Autodesk Fusion 360 part; units mm, degrees
(part 5 of 7)
sketch "Sketch16" plane through (0, 0, 15.5) normal (0, 0, 1) x (-1, 0, 0)
  arc A0 (-2.994408, 1.281873) -> (-3.212089, 0.540519) centre (0, 0) ccw
  line L0 (-3.212089, 0.540519) -> (-3.686686, 0.620382)
  spline S0 degree 5 poles (-3.686686, 0.620382) (-3.689992, 0.620938) (-3.696617, 0.621933) (-3.706589, 0.62307) (-3.719953, 0.62391) (-3.736756, 0.624036) (-3.753636, 0.623493) (-3.770571, 0.622533) (-3.787545, 0.621343) (-3.804547, 0.619993) (-3.821576, 0.618478) (-3.83863, 0.616745) (-3.855711, 0.614726) (-3.87282, 0.612373) (-3.889954, 0.609683) (-3.907112, 0.606681) (-3.924288, 0.603406) (-3.941479, 0.599899) (-3.958682, 0.596191) (-3.975894, 0.592292) (-3.993115, 0.5882) (-4.010344, 0.583904) (-4.02758, 0.579395) (-4.044821, 0.574666) (-4.062068, 0.56972) (-4.079318, 0.564562) (-4.096569, 0.559203) (-4.11382, 0.553651) (-4.13107, 0.547913) (-4.148317, 0.541992) (-4.165561, 0.535888) (-4.182799, 0.529602) (-4.200032, 0.523132) (-4.217258, 0.51648) (-4.234476, 0.509646) (-4.251685, 0.502632) (-4.268884, 0.495443) (-4.286072, 0.48808) (-4.303247, 0.480546) (-4.320409, 0.472843) (-4.337557, 0.46497) (-4.35469, 0.45693) (-4.371806, 0.448723) (-4.388905, 0.440351) (-4.405986, 0.431813) (-4.423048, 0.423112) (-4.44009, 0.414249) (-4.457112, 0.405224) (-4.474111, 0.396041) (-4.491087, 0.386698) (-4.50804, 0.377198) (-4.524969, 0.36754) (-4.541872, 0.357727) (-4.558748, 0.347759) (-4.575598, 0.337636) (-4.592419, 0.32736) (-4.609212, 0.316932) (-4.625974, 0.306352) (-4.642706, 0.295621) (-4.659407, 0.28474) (-4.676075, 0.273709) (-4.69271, 0.26253) (-4.709312, 0.251204) (-4.725879, 0.23973) (-4.74241, 0.22811) (-4.758905, 0.216344) (-4.775362, 0.204434) (-4.79178, 0.192379) (-4.80816, 0.180181) (-4.824499, 0.16784) (-4.840799, 0.155357) (-4.853807, 0.145257) (-4.863544, 0.137618) (-4.870028, 0.132497) (-4.873268, 0.12993) knots 0 0 0 0 0 0 0.01428571 0.02857143 0.04285714 0.05714286 0.07142857 0.08571429 0.1 0.11428571 0.12857143 0.14285714 0.15714286 0.17142857 0.18571429 0.2 0.21428571 0.22857143 0.24285714 0.25714286 0.27142857 0.28571429 0.3 0.31428571 0.32857143 0.34285714 0.35714286 0.37142857 0.38571429 0.4 0.41428571 0.42857143 0.44285714 0.45714286 0.47142857 0.48571429 0.5 0.51428571 0.52857143 0.54285714 0.55714286 0.57142857 0.58571429 0.6 0.61428571 0.62857143 0.64285714 0.65714286 0.67142857 0.68571429 0.7 0.71428571 0.72857143 0.74285714 0.75714286 0.77142857 0.78571429 0.8 0.81428571 0.82857143 0.84285714 0.85714286 0.87142857 0.88571429 0.9 0.91428571 0.92857143 0.94285714 0.95714286 0.97142857 0.98571429 1 1 1 1 1 1
  arc A1 (-4.873268, 0.12993) -> (-4.873268, -0.12993) centre (0, 0) ccw
  spline S1 degree 5 poles (-4.873268, -0.12993) (-4.870028, -0.132497) (-4.863544, -0.137618) (-4.853807, -0.145257) (-4.840799, -0.155357) (-4.824499, -0.16784) (-4.80816, -0.180181) (-4.79178, -0.192379) (-4.775362, -0.204434) (-4.758905, -0.216344) (-4.74241, -0.22811) (-4.725879, -0.23973) (-4.709312, -0.251204) (-4.69271, -0.26253) (-4.676075, -0.273709) (-4.659407, -0.28474) (-4.642706, -0.295621) (-4.625974, -0.306352) (-4.609212, -0.316932) (-4.592419, -0.32736) (-4.575598, -0.337636) (-4.558748, -0.347759) (-4.541872, -0.357727) (-4.524969, -0.36754) (-4.50804, -0.377198) (-4.491087, -0.386698) (-4.474111, -0.396041) (-4.457112, -0.405224) (-4.44009, -0.414249) (-4.423048, -0.423112) (-4.405986, -0.431813) (-4.388905, -0.440351) (-4.371806, -0.448723) (-4.35469, -0.45693) (-4.337557, -0.46497) (-4.320409, -0.472843) (-4.303247, -0.480546) (-4.286072, -0.48808) (-4.268884, -0.495443) (-4.251685, -0.502632) (-4.234476, -0.509646) (-4.217258, -0.51648) (-4.200032, -0.523132) (-4.182799, -0.529602) (-4.165561, -0.535888) (-4.148317, -0.541992) (-4.13107, -0.547913) (-4.11382, -0.553651) (-4.096569, -0.559203) (-4.079318, -0.564562) (-4.062068, -0.56972) (-4.044821, -0.574666) (-4.02758, -0.579395) (-4.010344, -0.583904) (-3.993115, -0.5882) (-3.975894, -0.592292) (-3.958682, -0.596191) (-3.941479, -0.599899) (-3.924288, -0.603406) (-3.907112, -0.606681) (-3.889954, -0.609683) (-3.87282, -0.612373) (-3.855711, -0.614726) (-3.83863, -0.616745) (-3.821576, -0.618478) (-3.804547, -0.619993) (-3.787545, -0.621343) (-3.770571, -0.622533) (-3.753636, -0.623493) (-3.736756, -0.624036) (-3.719953, -0.62391) (-3.706589, -0.62307) (-3.696617, -0.621933) (-3.689992, -0.620938) (-3.686686, -0.620382) knots -1 -1 -1 -1 -1 -1 -0.98571429 -0.97142857 -0.95714286 -0.94285714 -0.92857143 -0.91428571 -0.9 -0.88571429 -0.87142857 -0.85714286 -0.84285714 -0.82857143 -0.81428571 -0.8 -0.78571429 -0.77142857 -0.75714286 -0.74285714 -0.72857143 -0.71428571 -0.7 -0.68571429 -0.67142857 -0.65714286 -0.64285714 -0.62857143 -0.61428571 -0.6 -0.58571429 -0.57142857 -0.55714286 -0.54285714 -0.52857143 -0.51428571 -0.5 -0.48571429 -0.47142857 -0.45714286 -0.44285714 -0.42857143 -0.41428571 -0.4 -0.38571429 -0.37142857 -0.35714286 -0.34285714 -0.32857143 -0.31428571 -0.3 -0.28571429 -0.27142857 -0.25714286 -0.24285714 -0.22857143 -0.21428571 -0.2 -0.18571429 -0.17142857 -0.15714286 -0.14285714 -0.12857143 -0.11428571 -0.1 -0.08571429 -0.07142857 -0.05714286 -0.04285714 -0.02857143 -0.01428571 0 0 0 0 0 0
  line L1 (-3.686686, -0.620382) -> (-3.212089, -0.540519)
  arc A2 (-3.212089, -0.540519) -> (-2.994408, -1.281873) centre (0, 0) ccw
  line L2 (-2.994408, -1.281873) -> (-3.436842, -1.471275)
  spline S2 degree 5 poles (-3.436842, -1.471275) (-3.439924, -1.472594) (-3.446034, -1.475339) (-3.455038, -1.479774) (-3.466735, -1.486292) (-3.480939, -1.49527) (-3.494845, -1.504853) (-3.508573, -1.514816) (-3.522209, -1.524994) (-3.535783, -1.535322) (-3.549289, -1.545803) (-3.562699, -1.556481) (-3.575976, -1.567415) (-3.589097, -1.578644) (-3.602057, -1.59017) (-3.614868, -1.601972) (-3.627547, -1.614013) (-3.640113, -1.626257) (-3.652581, -1.638677) (-3.664953, -1.651263) (-3.677227, -1.664016) (-3.689398, -1.676944) (-3.70146, -1.690056) (-3.713408, -1.703356) (-3.725243, -1.716841) (-3.736966, -1.730506) (-3.748581, -1.744341) (-3.760092, -1.758338) (-3.771502, -1.772491) (-3.78281, -1.786797) (-3.794016, -1.801254) (-3.805119, -1.815862) (-3.816119, -1.830622) (-3.827013, -1.845531) (-3.837803, -1.860589) (-3.848489, -1.875793) (-3.85907, -1.89114) (-3.869549, -1.906626) (-3.879925, -1.92225) (-3.890197, -1.938009) (-3.900367, -1.953902) (-3.910433, -1.969929) (-3.920395, -1.986087) (-3.930253, -2.002375) (-3.940007, -2.018792) (-3.949657, -2.035336) (-3.959202, -2.052006) (-3.968642, -2.0688) (-3.977977, -2.085716) (-3.987208, -2.102754) (-3.996333, -2.119912) (-4.005353, -2.137188) (-4.014268, -2.154582) (-4.023076, -2.172092) (-4.031778, -2.189717) (-4.040373, -2.207456) (-4.048862, -2.225308) (-4.057243, -2.243271) (-4.065518, -2.261345) (-4.073684, -2.279527) (-4.081743, -2.297818) (-4.089694, -2.316216) (-4.097536, -2.33472) (-4.10527, -2.35333) (-4.112895, -2.372043) (-4.12041, -2.390858) (-4.127815, -2.409775) (-4.13511, -2.428793) (-4.142295, -2.447909) (-4.149368, -2.467125) (-4.156332, -2.486438) (-4.161814, -2.501968) (-4.165876, -2.513659) (-4.168562, -2.521472) (-4.1699, -2.525384) knots 0 0 0 0 0 0 0.01428571 0.02857143 0.04285714 0.05714286 0.07142857 0.08571429 0.1 0.11428571 0.12857143 0.14285714 0.15714286 0.17142857 0.18571429 0.2 0.21428571 0.22857143 0.24285714 0.25714286 0.27142857 0.28571429 0.3 0.31428571 0.32857143 0.34285714 0.35714286 0.37142857 0.38571429 0.4 0.41428571 0.42857143 0.44285714 0.45714286 0.47142857 0.48571429 0.5 0.51428571 0.52857143 0.54285714 0.55714286 0.57142857 0.58571429 0.6 0.61428571 0.62857143 0.64285714 0.65714286 0.67142857 0.68571429 0.7 0.71428571 0.72857143 0.74285714 0.75714286 0.77142857 0.78571429 0.8 0.81428571 0.82857143 0.84285714 0.85714286 0.87142857 0.88571429 0.9 0.91428571 0.92857143 0.94285714 0.95714286 0.97142857 0.98571429 1 1 1 1 1 1
  arc A3 (-4.1699, -2.525384) -> (-4.029409, -2.743992) centre (0, 0) ccw
  spline S3 degree 5 poles (-4.029409, -2.743992) (-4.025295, -2.7444) (-4.017072, -2.745203) (-4.00475, -2.746364) (-3.988346, -2.747828) (-3.967886, -2.749518) (-3.947468, -2.751065) (-3.927094, -2.752472) (-3.906765, -2.753736) (-3.886481, -2.754858) (-3.866244, -2.755839) (-3.846055, -2.756677) (-3.825914, -2.757372) (-3.805825, -2.757925) (-3.785786, -2.758336) (-3.765801, -2.758604) (-3.745869, -2.758728) (-3.725991, -2.75871) (-3.70617, -2.758548) (-3.686405, -2.758242) (-3.666698, -2.757793) (-3.647051, -2.757199) (-3.627464, -2.756461) (-3.607939, -2.755578) (-3.588476, -2.75455) (-3.569078, -2.753376) (-3.549746, -2.752057) (-3.53048, -2.750593) (-3.511282, -2.748982) (-3.492154, -2.747225) (-3.473096, -2.74532) (-3.45411, -2.743268) (-3.435199, -2.741067) (-3.416363, -2.738717) (-3.397603, -2.736218) (-3.378921, -2.73357) (-3.360319, -2.730772) (-3.341797, -2.727825) (-3.323357, -2.724726) (-3.305001, -2.721476) (-3.286733, -2.718072) (-3.268553, -2.714512) (-3.250465, -2.710796) (-3.23247, -2.706922) (-3.21457, -2.70289) (-3.196764, -2.698702) (-3.179053, -2.694359) (-3.16144, -2.68986) (-3.143925, -2.685204) (-3.126515, -2.680386) (-3.109215, -2.675398) (-3.092032, -2.670235) (-3.074971, -2.664892) (-3.058034, -2.659367) (-3.041218, -2.653666) (-3.024518, -2.647799) (-3.00793, -2.641773) (-2.991453, -2.635592) (-2.975095, -2.629247) (-2.958875, -2.622717) (-2.942818, -2.615966) (-2.92695, -2.608965) (-2.911285, -2.601695) (-2.895823, -2.594159) (-2.880539, -2.586397) (-2.865395, -2.578465) (-2.850362, -2.570408) (-2.835439, -2.562233) (-2.820673, -2.553885) (-2.80618, -2.545216) (-2.792112, -2.536025) (-2.781324, -2.528093) (-2.77355, -2.521745) (-2.768515, -2.517327) (-2.766034, -2.515072) knots -1 -1 -1 -1 -1 -1 -0.98571429 -0.97142857 -0.95714286 -0.94285714 -0.92857143 -0.91428571 -0.9 -0.88571429 -0.87142857 -0.85714286 -0.84285714 -0.82857143 -0.81428571 -0.8 -0.78571429 -0.77142857 -0.75714286 -0.74285714 -0.72857143 -0.71428571 -0.7 -0.68571429 -0.67142857 -0.65714286 -0.64285714 -0.62857143 -0.61428571 -0.6 -0.58571429 -0.57142857 -0.55714286 -0.54285714 -0.52857143 -0.51428571 -0.5 -0.48571429 -0.47142857 -0.45714286 -0.44285714 -0.42857143 -0.41428571 -0.4 -0.38571429 -0.37142857 -0.35714286 -0.34285714 -0.32857143 -0.31428571 -0.3 -0.28571429 -0.27142857 -0.25714286 -0.24285714 -0.22857143 -0.21428571 -0.2 -0.18571429 -0.17142857 -0.15714286 -0.14285714 -0.12857143 -0.11428571 -0.1 -0.08571429 -0.07142857 -0.05714286 -0.04285714 -0.02857143 -0.01428571 0 0 0 0 0 0
  line L3 (-2.766034, -2.515072) -> (-2.409955, -2.1913)
  arc A4 (-2.409955, -2.1913) -> (-1.826023, -2.69728) centre (0, 0) ccw
  line L4 (-1.826023, -2.69728) -> (-2.095824, -3.095812)
  spline S4 degree 5 poles (-2.095824, -3.095812) (-2.097704, -3.098588) (-2.10136, -3.104201) (-2.106537, -3.112799) (-2.112853, -3.124607) (-2.119948, -3.139839) (-2.126466, -3.155419) (-2.132628, -3.171222) (-2.138596, -3.187157) (-2.144432, -3.203184) (-2.150128, -3.219302) (-2.155636, -3.235535) (-2.160894, -3.251912) (-2.165861, -3.268452) (-2.170533, -3.285156) (-2.174929, -3.30201) (-2.179085, -3.318994) (-2.183037, -3.336088) (-2.186811, -3.353277) (-2.190414, -3.370554) (-2.193845, -3.387919) (-2.197095, -3.405375) (-2.200153, -3.422926) (-2.203014, -3.440574) (-2.205679, -3.458317) (-2.208154, -3.47615) (-2.210445, -3.494069) (-2.212562, -3.512068) (-2.214508, -3.530142) (-2.216286, -3.548291) (-2.217898, -3.566511) (-2.219341, -3.584803) (-2.220614, -3.603166) (-2.221719, -3.621599) (-2.222655, -3.6401) (-2.223424, -3.658668) (-2.224029, -3.677299) (-2.224472, -3.695992) (-2.224754, -3.714745) (-2.224875, -3.733556) (-2.224838, -3.752425) (-2.224642, -3.771349) (-2.224287, -3.790328) (-2.223774, -3.80936) (-2.223104, -3.828444) (-2.222277, -3.847579) (-2.221294, -3.866763) (-2.220156, -3.885995) (-2.218864, -3.905273) (-2.217418, -3.924597) (-2.215819, -3.943964) (-2.214067, -3.963375) (-2.212162, -3.982827) (-2.210105, -4.002319) (-2.207897, -4.021851) (-2.205537, -4.041421) (-2.203027, -4.061028) (-2.200366, -4.080671) (-2.197556, -4.100349) (-2.194596, -4.12006) (-2.191486, -4.139805) (-2.188228, -4.15958) (-2.184822, -4.179387) (-2.181267, -4.199223) (-2.177564, -4.219088) (-2.173714, -4.23898) (-2.169716, -4.258897) (-2.165572, -4.27884) (-2.16128, -4.298806) (-2.156842, -4.318795) (-2.152259, -4.338808) (-2.148475, -4.354836) (-2.145571, -4.366867) (-2.143607, -4.374892) (-2.142617, -4.378906) knots 0 0 0 0 0 0 0.01428571 0.02857143 0.04285714 0.05714286 0.07142857 0.08571429 0.1 0.11428571 0.12857143 0.14285714 0.15714286 0.17142857 0.18571429 0.2 0.21428571 0.22857143 0.24285714 0.25714286 0.27142857 0.28571429 0.3 0.31428571 0.32857143 0.34285714 0.35714286 0.37142857 0.38571429 0.4 0.41428571 0.42857143 0.44285714 0.45714286 0.47142857 0.48571429 0.5 0.51428571 0.52857143 0.54285714 0.55714286 0.57142857 0.58571429 0.6 0.61428571 0.62857143 0.64285714 0.65714286 0.67142857 0.68571429 0.7 0.71428571 0.72857143 0.74285714 0.75714286 0.77142857 0.78571429 0.8 0.81428571 0.82857143 0.84285714 0.85714286 0.87142857 0.88571429 0.9 0.91428571 0.92857143 0.94285714 0.95714286 0.97142857 0.98571429 1 1 1 1 1 1
  arc A5 (-2.142617, -4.378906) -> (-1.90624, -4.486856) centre (0, 0) ccw
  spline S5 degree 5 poles (-1.90624, -4.486856) (-1.902559, -4.484975) (-1.895207, -4.481204) (-1.884213, -4.47552) (-1.869622, -4.467883) (-1.851496, -4.458242) (-1.833483, -4.448506) (-1.815583, -4.438674) (-1.797798, -4.428747) (-1.780127, -4.418725) (-1.762573, -4.408608) (-1.745135, -4.398398) (-1.727816, -4.388095) (-1.710616, -4.377699) (-1.693537, -4.36721) (-1.676579, -4.356631) (-1.659744, -4.345959) (-1.643032, -4.335197) (-1.626445, -4.324345) (-1.609983, -4.313402) (-1.593647, -4.30237) (-1.57744, -4.291248) (-1.561362, -4.280037) (-1.545413, -4.268738) (-1.529597, -4.257351) (-1.513912, -4.245877) (-1.498362, -4.234316) (-1.482946, -4.222668) (-1.467666, -4.210933) (-1.452525, -4.199113) (-1.437522, -4.187208) (-1.42266, -4.175217) (-1.407941, -4.163141) (-1.393365, -4.150981) (-1.378934, -4.138736) (-1.36465, -4.126408) (-1.350513, -4.113997) (-1.336525, -4.101504) (-1.322688, -4.088928) (-1.309003, -4.07627) (-1.295475, -4.063529) (-1.282106, -4.050706) (-1.268898, -4.037801) (-1.255855, -4.024813) (-1.242975, -4.011743) (-1.23026, -3.998594) (-1.217709, -3.985365) (-1.205324, -3.972058) (-1.193107, -3.958672) (-1.181066, -3.945206) (-1.169209, -3.931657) (-1.157545, -3.918024) (-1.146081, -3.904305) (-1.134819, -3.8905) (-1.123755, -3.876612) (-1.112878, -3.862648) (-1.102181, -3.848611) (-1.091662, -3.834503) (-1.081331, -3.820322) (-1.071217, -3.806058) (-1.061358, -3.791698) (-1.051794, -3.77723) (-1.042546, -3.762644) (-1.033613, -3.747946) (-1.024952, -3.733153) (-1.0165, -3.718293) (-1.00821, -3.703387) (-1.000076, -3.688442) (-0.992167, -3.673436) (-0.984661, -3.658307) (-0.977796, -3.64297) (-0.973009, -3.630464) (-0.9699, -3.620921) (-0.968053, -3.614482) (-0.967186, -3.611244) knots -1 -1 -1 -1 -1 -1 -0.98571429 -0.97142857 -0.95714286 -0.94285714 -0.92857143 -0.91428571 -0.9 -0.88571429 -0.87142857 -0.85714286 -0.84285714 -0.82857143 -0.81428571 -0.8 -0.78571429 -0.77142857 -0.75714286 -0.74285714 -0.72857143 -0.71428571 -0.7 -0.68571429 -0.67142857 -0.65714286 -0.64285714 -0.62857143 -0.61428571 -0.6 -0.58571429 -0.57142857 -0.55714286 -0.54285714 -0.52857143 -0.51428571 -0.5 -0.48571429 -0.47142857 -0.45714286 -0.44285714 -0.42857143 -0.41428571 -0.4 -0.38571429 -0.37142857 -0.35714286 -0.34285714 -0.32857143 -0.31428571 -0.3 -0.28571429 -0.27142857 -0.25714286 -0.24285714 -0.22857143 -0.21428571 -0.2 -0.18571429 -0.17142857 -0.15714286 -0.14285714 -0.12857143 -0.11428571 -0.1 -0.08571429 -0.07142857 -0.05714286 -0.04285714 -0.02857143 -0.01428571 0 0 0 0 0 0
  line L5 (-0.967186, -3.611244) -> (-0.842677, -3.146359)
  arc A6 (-0.842677, -3.146359) -> (-0.077889, -3.256319) centre (0, 0) ccw
  line L6 (-0.077889, -3.256319) -> (-0.089397, -3.737451)
  spline S6 degree 5 poles (-0.089397, -3.737451) (-0.089477, -3.740802) (-0.089519, -3.747501) (-0.089225, -3.757533) (-0.088155, -3.770881) (-0.085889, -3.787531) (-0.082949, -3.804162) (-0.079588, -3.820788) (-0.075995, -3.837419) (-0.072239, -3.854057) (-0.068316, -3.870696) (-0.064174, -3.88733) (-0.059744, -3.90395) (-0.05498, -3.92055) (-0.049879, -3.937127) (-0.044466, -3.953683) (-0.038779, -3.970218) (-0.032862, -3.986735) (-0.026744, -4.003235) (-0.020435, -4.019718) (-0.013933, -4.036181) (-0.007229, -4.052623) (-0.000313, -4.069041) (0.006821, -4.085434) (0.014172, -4.101801) (0.021731, -4.118142) (0.029491, -4.134455) (0.037442, -4.15074) (0.045577, -4.166998) (0.053892, -4.183227) (0.062387, -4.199426) (0.071063, -4.215595) (0.079919, -4.231731) (0.088956, -4.247835) (0.098171, -4.263905) (0.107561, -4.279941) (0.117125, -4.295942) (0.126859, -4.311907) (0.136761, -4.327835) (0.146829, -4.343726) (0.157061, -4.359579) (0.167458, -4.375393) (0.178017, -4.391167) (0.188738, -4.406901) (0.199619, -4.422593) (0.21066, -4.438243) (0.221859, -4.45385) (0.233213, -4.469414) (0.244723, -4.484933) (0.256386, -4.500408) (0.268203, -4.515836) (0.280171, -4.531218) (0.29229, -4.546552) (0.304558, -4.561838) (0.316976, -4.577076) (0.329541, -4.592263) (0.342253, -4.607401) (0.355111, -4.622487) (0.368114, -4.637521) (0.381261, -4.652503) (0.394552, -4.667432) (0.407984, -4.682307) (0.421558, -4.697128) (0.435273, -4.711894) (0.449128, -4.726603) (0.463121, -4.741255) (0.477252, -4.75585) (0.491521, -4.770385) (0.505925, -4.784862) (0.520466, -4.799279) (0.535141, -4.813636) (0.54699, -4.825074) (0.555937, -4.833626) (0.561928, -4.839315) (0.564931, -4.842156) knots 0 0 0 0 0 0 0.01428571 0.02857143 0.04285714 0.05714286 0.07142857 0.08571429 0.1 0.11428571 0.12857143 0.14285714 0.15714286 0.17142857 0.18571429 0.2 0.21428571 0.22857143 0.24285714 0.25714286 0.27142857 0.28571429 0.3 0.31428571 0.32857143 0.34285714 0.35714286 0.37142857 0.38571429 0.4 0.41428571 0.42857143 0.44285714 0.45714286 0.47142857 0.48571429 0.5 0.51428571 0.52857143 0.54285714 0.55714286 0.57142857 0.58571429 0.6 0.61428571 0.62857143 0.64285714 0.65714286 0.67142857 0.68571429 0.7 0.71428571 0.72857143 0.74285714 0.75714286 0.77142857 0.78571429 0.8 0.81428571 0.82857143 0.84285714 0.85714286 0.87142857 0.88571429 0.9 0.91428571 0.92857143 0.94285714 0.95714286 0.97142857 0.98571429 1 1 1 1 1 1
  arc A7 (0.564931, -4.842156) -> (0.822146, -4.805174) centre (0, 0) ccw
  spline S7 degree 5 poles (0.822146, -4.805174) (0.824226, -4.801602) (0.828372, -4.794455) (0.834548, -4.783729) (0.842694, -4.769417) (0.85273, -4.751506) (0.86262, -4.733577) (0.872362, -4.715629) (0.881958, -4.697662) (0.891405, -4.679677) (0.900703, -4.661676) (0.909852, -4.643659) (0.918852, -4.625628) (0.927701, -4.607583) (0.936398, -4.589526) (0.944944, -4.571458) (0.953338, -4.553379) (0.961578, -4.53529) (0.969665, -4.517193) (0.977598, -4.499087) (0.985375, -4.480974) (0.992997, -4.462856) (1.000462, -4.444732) (1.00777, -4.426605) (1.014919, -4.408474) (1.02191, -4.390342) (1.028742, -4.372208) (1.035413, -4.354075) (1.041923, -4.335943) (1.048271, -4.317813) (1.054455, -4.299686) (1.060475, -4.281564) (1.066329, -4.263447) (1.072016, -4.245337) (1.077536, -4.227235) (1.082888, -4.209141) (1.088071, -4.191057) (1.093084, -4.172985) (1.097926, -4.154924) (1.102594, -4.136877) (1.107087, -4.118845) (1.111401, -4.10083) (1.115535, -4.082832) (1.119486, -4.064854) (1.123255, -4.046897) (1.126842, -4.02896) (1.130249, -4.011046) (1.133473, -3.993155) (1.136514, -3.975289) (1.139363, -3.95745) (1.142013, -3.939642) (1.144455, -3.921867) (1.146682, -3.904128) (1.148692, -3.886426) (1.150492, -3.868762) (1.152092, -3.851134) (1.153502, -3.833541) (1.154724, -3.815986) (1.155748, -3.798471) (1.156546, -3.781003) (1.157076, -3.763593) (1.157299, -3.74625) (1.157194, -3.728981) (1.156762, -3.711786) (1.15605, -3.694659) (1.155126, -3.677588) (1.154042, -3.660567) (1.152805, -3.643596) (1.151345, -3.626697) (1.14948, -3.609912) (1.146964, -3.593298) (1.14423, -3.580189) (1.141686, -3.57048) (1.139759, -3.564065) (1.138738, -3.560872) knots -1 -1 -1 -1 -1 -1 -0.98571429 -0.97142857 -0.95714286 -0.94285714 -0.92857143 -0.91428571 -0.9 -0.88571429 -0.87142857 -0.85714286 -0.84285714 -0.82857143 -0.81428571 -0.8 -0.78571429 -0.77142857 -0.75714286 -0.74285714 -0.72857143 -0.71428571 -0.7 -0.68571429 -0.67142857 -0.65714286 -0.64285714 -0.62857143 -0.61428571 -0.6 -0.58571429 -0.57142857 -0.55714286 -0.54285714 -0.52857143 -0.51428571 -0.5 -0.48571429 -0.47142857 -0.45714286 -0.44285714 -0.42857143 -0.41428571 -0.4 -0.38571429 -0.37142857 -0.35714286 -0.34285714 -0.32857143 -0.31428571 -0.3 -0.28571429 -0.27142857 -0.25714286 -0.24285714 -0.22857143 -0.21428571 -0.2 -0.18571429 -0.17142857 -0.15714286 -0.14285714 -0.12857143 -0.11428571 -0.1 -0.08571429 -0.07142857 -0.05714286 -0.04285714 -0.02857143 -0.01428571 0 0 0 0 0 0
  line L7 (1.138738, -3.560872) -> (0.992145, -3.102471)
  arc A8 (0.992145, -3.102471) -> (1.694974, -2.781499) centre (0, 0) ccw
  line L8 (1.694974, -2.781499) -> (1.945413, -3.192475)
  spline S8 degree 5 poles (1.945413, -3.192475) (1.947157, -3.195338) (1.950744, -3.200996) (1.956415, -3.209277) (1.964531, -3.219927) (1.97544, -3.232709) (1.986904, -3.24511) (1.99872, -3.25728) (2.010735, -3.269328) (2.022889, -3.281294) (2.035185, -3.293172) (2.047663, -3.304925) (2.060375, -3.316512) (2.073357, -3.327901) (2.086611, -3.339089) (2.100115, -3.35009) (2.113839, -3.360926) (2.127746, -3.371622) (2.141814, -3.382195) (2.156033, -3.392649) (2.170403, -3.402984) (2.184932, -3.413192) (2.199626, -3.423264) (2.214491, -3.433198) (2.229523, -3.442993) (2.244717, -3.452652) (2.260065, -3.462181) (2.275558, -3.471582) (2.291191, -3.480861) (2.30696, -3.490018) (2.322865, -3.499053) (2.338905, -3.507964) (2.355079, -3.516751) (2.371387, -3.525413) (2.387828, -3.53395) (2.404397, -3.542363) (2.421094, -3.550653) (2.437914, -3.558821) (2.454855, -3.566868) (2.471916, -3.574793) (2.489095, -3.582598) (2.50639, -3.59028) (2.523801, -3.597842) (2.541327, -3.605282) (2.558965, -3.6126) (2.576714, -3.619796) (2.594573, -3.626872) (2.612539, -3.633826) (2.630612, -3.640659) (2.64879, -3.647371) (2.667072, -3.653962) (2.685456, -3.660431) (2.703941, -3.666779) (2.722527, -3.673006) (2.741211, -3.679111) (2.759993, -3.685094) (2.778871, -3.690956) (2.797844, -3.696696) (2.816911, -3.702314) (2.836071, -3.707809) (2.855322, -3.713183) (2.874665, -3.718435) (2.894096, -3.723564) (2.913617, -3.728571) (2.933225, -3.733455) (2.952918, -3.738216) (2.972697, -3.742853) (2.992558, -3.747368) (3.012503, -3.751758) (3.03253, -3.756025) (3.052638, -3.760169) (3.068789, -3.763386) (3.080939, -3.765742) (3.089055, -3.767289) (3.093118, -3.768056) knots 0 0 0 0 0 0 0.01428571 0.02857143 0.04285714 0.05714286 0.07142857 0.08571429 0.1 0.11428571 0.12857143 0.14285714 0.15714286 0.17142857 0.18571429 0.2 0.21428571 0.22857143 0.24285714 0.25714286 0.27142857 0.28571429 0.3 0.31428571 0.32857143 0.34285714 0.35714286 0.37142857 0.38571429 0.4 0.41428571 0.42857143 0.44285714 0.45714286 0.47142857 0.48571429 0.5 0.51428571 0.52857143 0.54285714 0.55714286 0.57142857 0.58571429 0.6 0.61428571 0.62857143 0.64285714 0.65714286 0.67142857 0.68571429 0.7 0.71428571 0.72857143 0.74285714 0.75714286 0.77142857 0.78571429 0.8 0.81428571 0.82857143 0.84285714 0.85714286 0.87142857 0.88571429 0.9 0.91428571 0.92857143 0.94285714 0.95714286 0.97142857 0.98571429 1 1 1 1 1 1
  arc A9 (3.093118, -3.768056) -> (3.289506, -3.597884) centre (0, 0) ccw
  spline S9 degree 5 poles (3.289506, -3.597884) (3.289325, -3.593754) (3.288949, -3.585501) (3.288345, -3.573139) (3.28746, -3.556694) (3.28622, -3.536201) (3.284847, -3.515771) (3.283339, -3.495405) (3.281698, -3.475102) (3.279922, -3.454865) (3.278012, -3.434695) (3.275968, -3.414591) (3.273791, -3.394557) (3.271479, -3.374593) (3.269034, -3.3547) (3.266454, -3.33488) (3.263741, -3.315133) (3.260894, -3.295461) (3.257913, -3.275864) (3.254797, -3.256344) (3.251548, -3.236902) (3.248164, -3.217539) (3.244646, -3.198256) (3.240993, -3.179055) (3.237206, -3.159938) (3.233284, -3.140904) (3.229227, -3.121956) (3.225036, -3.103095) (3.220709, -3.084321) (3.216247, -3.065638) (3.21165, -3.047045) (3.206916, -3.028545) (3.202047, -3.010139) (3.19704, -2.991829) (3.191897, -2.973616) (3.186617, -2.955501) (3.1812, -2.937486) (3.175646, -2.919572) (3.169955, -2.901761) (3.164126, -2.884055) (3.158157, -2.866457) (3.152046, -2.848969) (3.145793, -2.831594) (3.139398, -2.814333) (3.132859, -2.797189) (3.12618, -2.78016) (3.119361, -2.763248) (3.112401, -2.746454) (3.1053, -2.72978) (3.098053, -2.713233) (3.090654, -2.696819) (3.083098, -2.680546) (3.075381, -2.664419) (3.067502, -2.64844) (3.059466, -2.632606) (3.051282, -2.616912) (3.042957, -2.60135) (3.034493, -2.585921) (3.025886, -2.570632) (3.017113, -2.555507) (3.008146, -2.540574) (2.998958, -2.525863) (2.989532, -2.511392) (2.979873, -2.497161) (2.970015, -2.483137) (2.960008, -2.469276) (2.949894, -2.455542) (2.939678, -2.441935) (2.929314, -2.428507) (2.91867, -2.415395) (2.907571, -2.402779) (2.898184, -2.393229) (2.890795, -2.386437) (2.885705, -2.382082) (2.883119, -2.379948) knots -1 -1 -1 -1 -1 -1 -0.98571429 -0.97142857 -0.95714286 -0.94285714 -0.92857143 -0.91428571 -0.9 -0.88571429 -0.87142857 -0.85714286 -0.84285714 -0.82857143 -0.81428571 -0.8 -0.78571429 -0.77142857 -0.75714286 -0.74285714 -0.72857143 -0.71428571 -0.7 -0.68571429 -0.67142857 -0.65714286 -0.64285714 -0.62857143 -0.61428571 -0.6 -0.58571429 -0.57142857 -0.55714286 -0.54285714 -0.52857143 -0.51428571 -0.5 -0.48571429 -0.47142857 -0.45714286 -0.44285714 -0.42857143 -0.41428571 -0.4 -0.38571429 -0.37142857 -0.35714286 -0.34285714 -0.32857143 -0.31428571 -0.3 -0.28571429 -0.27142857 -0.25714286 -0.24285714 -0.22857143 -0.21428571 -0.2 -0.18571429 -0.17142857 -0.15714286 -0.14285714 -0.12857143 -0.11428571 -0.1 -0.08571429 -0.07142857 -0.05714286 -0.04285714 -0.02857143 -0.01428571 0 0 0 0 0 0
  line L9 (2.883119, -2.379948) -> (2.511968, -2.073571)
  arc A10 (2.511968, -2.073571) -> (2.929695, -1.423574) centre (0, 0) ccw
  line L10 (2.929695, -1.423574) -> (3.362568, -1.633912)
  spline S10 degree 5 poles (3.362568, -1.633912) (3.365583, -1.635377) (3.371659, -1.638197) (3.380907, -1.642098) (3.393493, -1.646669) (3.40958, -1.651524) (3.425929, -1.655759) (3.442449, -1.659609) (3.45907, -1.663249) (3.475764, -1.666744) (3.49253, -1.670088) (3.509381, -1.67323) (3.526339, -1.676104) (3.543418, -1.678667) (3.560616, -1.680913) (3.577925, -1.682867) (3.595328, -1.684563) (3.61281, -1.686042) (3.630361, -1.687331) (3.647975, -1.688439) (3.665651, -1.689364) (3.683392, -1.690096) (3.7012, -1.690626) (3.719076, -1.690946) (3.737017, -1.691059) (3.755021, -1.69097) (3.773083, -1.690688) (3.7912, -1.690222) (3.809368, -1.689576) (3.827585, -1.688753) (3.845849, -1.687755) (3.86416, -1.68658) (3.882518, -1.685228) (3.90092, -1.683698) (3.919366, -1.681991) (3.937854, -1.68011) (3.956382, -1.678058) (3.974948, -1.675836) (3.99355, -1.673446) (4.012187, -1.670889) (4.030858, -1.668167) (4.049562, -1.665279) (4.068297, -1.662227) (4.087063, -1.659011) (4.105857, -1.655631) (4.124679, -1.65209) (4.143528, -1.648387) (4.162402, -1.644523) (4.1813, -1.640501) (4.200221, -1.63632) (4.219164, -1.63198) (4.238128, -1.627484) (4.257111, -1.62283) (4.276112, -1.61802) (4.295131, -1.613055) (4.314166, -1.607934) (4.333216, -1.602659) (4.352281, -1.59723) (4.371358, -1.591647) (4.390448, -1.585912) (4.409548, -1.580025) (4.428659, -1.573985) (4.44778, -1.567795) (4.466908, -1.561453) (4.486044, -1.554961) (4.505185, -1.548319) (4.524331, -1.541527) (4.54348, -1.534587) (4.562632, -1.527498) (4.581787, -1.52026) (4.600943, -1.512875) (4.61627, -1.506849) (4.627765, -1.502263) (4.635429, -1.499176) (4.639261, -1.497625) knots 0 0 0 0 0 0 0.01428571 0.02857143 0.04285714 0.05714286 0.07142857 0.08571429 0.1 0.11428571 0.12857143 0.14285714 0.15714286 0.17142857 0.18571429 0.2 0.21428571 0.22857143 0.24285714 0.25714286 0.27142857 0.28571429 0.3 0.31428571 0.32857143 0.34285714 0.35714286 0.37142857 0.38571429 0.4 0.41428571 0.42857143 0.44285714 0.45714286 0.47142857 0.48571429 0.5 0.51428571 0.52857143 0.54285714 0.55714286 0.57142857 0.58571429 0.6 0.61428571 0.62857143 0.64285714 0.65714286 0.67142857 0.68571429 0.7 0.71428571 0.72857143 0.74285714 0.75714286 0.77142857 0.78571429 0.8 0.81428571 0.82857143 0.84285714 0.85714286 0.87142857 0.88571429 0.9 0.91428571 0.92857143 0.94285714 0.95714286 0.97142857 0.98571429 1 1 1 1 1 1
  arc A11 (4.639261, -1.497625) -> (4.712472, -1.248291) centre (0, 0) ccw
  spline S11 degree 5 poles (4.712472, -1.248291) (4.710087, -1.244915) (4.705308, -1.238175) (4.698117, -1.228102) (4.688482, -1.214746) (4.676359, -1.198177) (4.664158, -1.181733) (4.651879, -1.165414) (4.639522, -1.149222) (4.627087, -1.133158) (4.614575, -1.117222) (4.601987, -1.101415) (4.589324, -1.085738) (4.576586, -1.070193) (4.563774, -1.05478) (4.550888, -1.039501) (4.53793, -1.024356) (4.524899, -1.009345) (4.511796, -0.994471) (4.498622, -0.979734) (4.485377, -0.965135) (4.472062, -0.950676) (4.458677, -0.936356) (4.445224, -0.922178) (4.431702, -0.908143) (4.418112, -0.894252) (4.404456, -0.880505) (4.390732, -0.866903) (4.376943, -0.853449) (4.363088, -0.840144) (4.349169, -0.826988) (4.335185, -0.813984) (4.321137, -0.801133) (4.307026, -0.788436) (4.292853, -0.775895) (4.278617, -0.763511) (4.264321, -0.751284) (4.249964, -0.739216) (4.235547, -0.727309) (4.22107, -0.715566) (4.206534, -0.703988) (4.191939, -0.69258) (4.177285, -0.681344) (4.162573, -0.670281) (4.147803, -0.659393) (4.132978, -0.648679) (4.118098, -0.638138) (4.103163, -0.627773) (4.088175, -0.617585) (4.073132, -0.607583) (4.058034, -0.597775) (4.04288, -0.58817) (4.027669, -0.578775) (4.012402, -0.569593) (3.997081, -0.560617) (3.981711, -0.551839) (3.966294, -0.543248) (3.950833, -0.534844) (3.935326, -0.526636) (3.919768, -0.518655) (3.904152, -0.51094) (3.888469, -0.503532) (3.872716, -0.496454) (3.856896, -0.489704) (3.841021, -0.483237) (3.825109, -0.476986) (3.809175, -0.470901) (3.793224, -0.464976) (3.777246, -0.459284) (3.761203, -0.454007) (3.745045, -0.449395) (3.731985, -0.446436) (3.722097, -0.444717) (3.71546, -0.443805) (3.712131, -0.443407) knots -1 -1 -1 -1 -1 -1 -0.98571429 -0.97142857 -0.95714286 -0.94285714 -0.92857143 -0.91428571 -0.9 -0.88571429 -0.87142857 -0.85714286 -0.84285714 -0.82857143 -0.81428571 -0.8 -0.78571429 -0.77142857 -0.75714286 -0.74285714 -0.72857143 -0.71428571 -0.7 -0.68571429 -0.67142857 -0.65714286 -0.64285714 -0.62857143 -0.61428571 -0.6 -0.58571429 -0.57142857 -0.55714286 -0.54285714 -0.52857143 -0.51428571 -0.5 -0.48571429 -0.47142857 -0.45714286 -0.44285714 -0.42857143 -0.41428571 -0.4 -0.38571429 -0.37142857 -0.35714286 -0.34285714 -0.32857143 -0.31428571 -0.3 -0.28571429 -0.27142857 -0.25714286 -0.24285714 -0.22857143 -0.21428571 -0.2 -0.18571429 -0.17142857 -0.15714286 -0.14285714 -0.12857143 -0.11428571 -0.1 -0.08571429 -0.07142857 -0.05714286 -0.04285714 -0.02857143 -0.01428571 0 0 0 0 0 0
  line L11 (3.712131, -0.443407) -> (3.234259, -0.386326)
  arc A12 (3.234259, -0.386326) -> (3.234259, 0.386326) centre (0, 0) ccw
  line L12 (3.234259, 0.386326) -> (3.712131, 0.443407)
  spline S12 degree 5 poles (3.712131, 0.443407) (3.71546, 0.443805) (3.722097, 0.444717) (3.731985, 0.446436) (3.745045, 0.449395) (3.761203, 0.454007) (3.777246, 0.459284) (3.793224, 0.464976) (3.809175, 0.470901) (3.825109, 0.476986) (3.841021, 0.483237) (3.856896, 0.489704) (3.872716, 0.496454) (3.888469, 0.503532) (3.904152, 0.51094) (3.919768, 0.518655) (3.935326, 0.526636) (3.950833, 0.534844) (3.966294, 0.543248) (3.981711, 0.551839) (3.997081, 0.560617) (4.012402, 0.569593) (4.027669, 0.578775) (4.04288, 0.58817) (4.058034, 0.597775) (4.073132, 0.607583) (4.088175, 0.617585) (4.103163, 0.627773) (4.118098, 0.638138) (4.132978, 0.648679) (4.147803, 0.659393) (4.162573, 0.670281) (4.177285, 0.681344) (4.191939, 0.69258) (4.206534, 0.703988) (4.22107, 0.715566) (4.235547, 0.727309) (4.249964, 0.739216) (4.264321, 0.751284) (4.278617, 0.763511) (4.292853, 0.775895) (4.307026, 0.788436) (4.321137, 0.801133) (4.335185, 0.813984) (4.349169, 0.826988) (4.363088, 0.840144) (4.376943, 0.853449) (4.390732, 0.866903) (4.404456, 0.880505) (4.418112, 0.894252) (4.431702, 0.908143) (4.445224, 0.922178) (4.458677, 0.936356) (4.472062, 0.950676) (4.485377, 0.965135) (4.498622, 0.979734) (4.511796, 0.994471) (4.524899, 1.009345) (4.53793, 1.024356) (4.550888, 1.039501) (4.563774, 1.05478) (4.576586, 1.070193) (4.589324, 1.085738) (4.601987, 1.101415) (4.614575, 1.117222) (4.627087, 1.133158) (4.639522, 1.149222) (4.651879, 1.165414) (4.664158, 1.181733) (4.676359, 1.198177) (4.688482, 1.214746) (4.698117, 1.228102) (4.705308, 1.238175) (4.710087, 1.244915) (4.712472, 1.248291) knots 0 0 0 0 0 0 0.01428571 0.02857143 0.04285714 0.05714286 0.07142857 0.08571429 0.1 0.11428571 0.12857143 0.14285714 0.15714286 0.17142857 0.18571429 0.2 0.21428571 0.22857143 0.24285714 0.25714286 0.27142857 0.28571429 0.3 0.31428571 0.32857143 0.34285714 0.35714286 0.37142857 0.38571429 0.4 0.41428571 0.42857143 0.44285714 0.45714286 0.47142857 0.48571429 0.5 0.51428571 0.52857143 0.54285714 0.55714286 0.57142857 0.58571429 0.6 0.61428571 0.62857143 0.64285714 0.65714286 0.67142857 0.68571429 0.7 0.71428571 0.72857143 0.74285714 0.75714286 0.77142857 0.78571429 0.8 0.81428571 0.82857143 0.84285714 0.85714286 0.87142857 0.88571429 0.9 0.91428571 0.92857143 0.94285714 0.95714286 0.97142857 0.98571429 1 1 1 1 1 1
  arc A13 (4.712472, 1.248291) -> (4.639261, 1.497625) centre (0, 0) ccw
  spline S13 degree 5 poles (4.639261, 1.497625) (4.635429, 1.499176) (4.627765, 1.502263) (4.61627, 1.506849) (4.600943, 1.512875) (4.581787, 1.52026) (4.562632, 1.527498) (4.54348, 1.534587) (4.524331, 1.541527) (4.505185, 1.548319) (4.486044, 1.554961) (4.466908, 1.561453) (4.44778, 1.567795) (4.428659, 1.573985) (4.409548, 1.580025) (4.390448, 1.585912) (4.371358, 1.591647) (4.352281, 1.59723) (4.333216, 1.602659) (4.314166, 1.607934) (4.295131, 1.613055) (4.276112, 1.61802) (4.257111, 1.62283) (4.238128, 1.627484) (4.219164, 1.63198) (4.200221, 1.63632) (4.1813, 1.640501) (4.162402, 1.644523) (4.143528, 1.648387) (4.124679, 1.65209) (4.105857, 1.655631) (4.087063, 1.659011) (4.068297, 1.662227) (4.049562, 1.665279) (4.030858, 1.668167) (4.012187, 1.670889) (3.99355, 1.673446) (3.974948, 1.675836) (3.956382, 1.678058) (3.937854, 1.68011) (3.919366, 1.681991) (3.90092, 1.683698) (3.882518, 1.685228) (3.86416, 1.68658) (3.845849, 1.687755) (3.827585, 1.688753) (3.809368, 1.689576) (3.7912, 1.690222) (3.773083, 1.690688) (3.755021, 1.69097) (3.737017, 1.691059) (3.719076, 1.690946) (3.7012, 1.690626) (3.683392, 1.690096) (3.665651, 1.689364) (3.647975, 1.688439) (3.630361, 1.687331) (3.61281, 1.686042) (3.595328, 1.684563) (3.577925, 1.682867) (3.560616, 1.680913) (3.543418, 1.678667) (3.526339, 1.676104) (3.509381, 1.67323) (3.49253, 1.670088) (3.475764, 1.666744) (3.45907, 1.663249) (3.442449, 1.659609) (3.425929, 1.655759) (3.40958, 1.651524) (3.393493, 1.646669) (3.380907, 1.642098) (3.371659, 1.638197) (3.365583, 1.635377) (3.362568, 1.633912) knots -1 -1 -1 -1 -1 -1 -0.98571429 -0.97142857 -0.95714286 -0.94285714 -0.92857143 -0.91428571 -0.9 -0.88571429 -0.87142857 -0.85714286 -0.84285714 -0.82857143 -0.81428571 -0.8 -0.78571429 -0.77142857 -0.75714286 -0.74285714 -0.72857143 -0.71428571 -0.7 -0.68571429 -0.67142857 -0.65714286 -0.64285714 -0.62857143 -0.61428571 -0.6 -0.58571429 -0.57142857 -0.55714286 -0.54285714 -0.52857143 -0.51428571 -0.5 -0.48571429 -0.47142857 -0.45714286 -0.44285714 -0.42857143 -0.41428571 -0.4 -0.38571429 -0.37142857 -0.35714286 -0.34285714 -0.32857143 -0.31428571 -0.3 -0.28571429 -0.27142857 -0.25714286 -0.24285714 -0.22857143 -0.21428571 -0.2 -0.18571429 -0.17142857 -0.15714286 -0.14285714 -0.12857143 -0.11428571 -0.1 -0.08571429 -0.07142857 -0.05714286 -0.04285714 -0.02857143 -0.01428571 0 0 0 0 0 0
  line L13 (3.362568, 1.633912) -> (2.929695, 1.423574)
  arc A14 (2.929695, 1.423574) -> (2.511968, 2.073571) centre (0, 0) ccw
  line L14 (2.511968, 2.073571) -> (2.883119, 2.379948)
  spline S14 degree 5 poles (2.883119, 2.379948) (2.885705, 2.382082) (2.890795, 2.386437) (2.898184, 2.393229) (2.907571, 2.402779) (2.91867, 2.415395) (2.929314, 2.428507) (2.939678, 2.441935) (2.949894, 2.455542) (2.960008, 2.469276) (2.970015, 2.483137) (2.979873, 2.497161) (2.989532, 2.511392) (2.998958, 2.525863) (3.008146, 2.540574) (3.017113, 2.555507) (3.025886, 2.570632) (3.034493, 2.585921) (3.042957, 2.60135) (3.051282, 2.616912) (3.059466, 2.632606) (3.067502, 2.64844) (3.075381, 2.664419) (3.083098, 2.680546) (3.090654, 2.696819) (3.098053, 2.713233) (3.1053, 2.72978) (3.112401, 2.746454) (3.119361, 2.763248) (3.12618, 2.78016) (3.132859, 2.797189) (3.139398, 2.814333) (3.145793, 2.831594) (3.152046, 2.848969) (3.158157, 2.866457) (3.164126, 2.884055) (3.169955, 2.901761) (3.175646, 2.919572) (3.1812, 2.937486) (3.186617, 2.955501) (3.191897, 2.973616) (3.19704, 2.991829) (3.202047, 3.010139) (3.206916, 3.028545) (3.21165, 3.047045) (3.216247, 3.065638) (3.220709, 3.084321) (3.225036, 3.103095) (3.229227, 3.121956) (3.233284, 3.140904) (3.237206, 3.159938) (3.240993, 3.179055) (3.244646, 3.198256) (3.248164, 3.217539) (3.251548, 3.236902) (3.254797, 3.256344) (3.257913, 3.275864) (3.260894, 3.295461) (3.263741, 3.315133) (3.266454, 3.33488) (3.269034, 3.3547) (3.271479, 3.374593) (3.273791, 3.394557) (3.275968, 3.414591) (3.278012, 3.434695) (3.279922, 3.454865) (3.281698, 3.475102) (3.283339, 3.495405) (3.284847, 3.515771) (3.28622, 3.536201) (3.28746, 3.556694) (3.288345, 3.573139) (3.288949, 3.585501) (3.289325, 3.593754) (3.289506, 3.597884) knots 0 0 0 0 0 0 0.01428571 0.02857143 0.04285714 0.05714286 0.07142857 0.08571429 0.1 0.11428571 0.12857143 0.14285714 0.15714286 0.17142857 0.18571429 0.2 0.21428571 0.22857143 0.24285714 0.25714286 0.27142857 0.28571429 0.3 0.31428571 0.32857143 0.34285714 0.35714286 0.37142857 0.38571429 0.4 0.41428571 0.42857143 0.44285714 0.45714286 0.47142857 0.48571429 0.5 0.51428571 0.52857143 0.54285714 0.55714286 0.57142857 0.58571429 0.6 0.61428571 0.62857143 0.64285714 0.65714286 0.67142857 0.68571429 0.7 0.71428571 0.72857143 0.74285714 0.75714286 0.77142857 0.78571429 0.8 0.81428571 0.82857143 0.84285714 0.85714286 0.87142857 0.88571429 0.9 0.91428571 0.92857143 0.94285714 0.95714286 0.97142857 0.98571429 1 1 1 1 1 1
  arc A15 (3.289506, 3.597884) -> (3.093118, 3.768056) centre (0, 0) ccw
  spline S15 degree 5 poles (3.093118, 3.768056) (3.089055, 3.767289) (3.080939, 3.765742) (3.068789, 3.763386) (3.052638, 3.760169) (3.03253, 3.756025) (3.012503, 3.751758) (2.992558, 3.747368) (2.972697, 3.742853) (2.952918, 3.738216) (2.933225, 3.733455) (2.913617, 3.728571) (2.894096, 3.723564) (2.874665, 3.718435) (2.855322, 3.713183) (2.836071, 3.707809) (2.816911, 3.702314) (2.797844, 3.696696) (2.778871, 3.690956) (2.759993, 3.685094) (2.741211, 3.679111) (2.722527, 3.673006) (2.703941, 3.666779) (2.685456, 3.660431) (2.667072, 3.653962) (2.64879, 3.647371) (2.630612, 3.640659) (2.612539, 3.633826) (2.594573, 3.626872) (2.576714, 3.619796) (2.558965, 3.6126) (2.541327, 3.605282) (2.523801, 3.597842) (2.50639, 3.59028) (2.489095, 3.582598) (2.471916, 3.574793) (2.454855, 3.566868) (2.437914, 3.558821) (2.421094, 3.550653) (2.404397, 3.542363) (2.387828, 3.53395) (2.371387, 3.525413) (2.355079, 3.516751) (2.338905, 3.507964) (2.322865, 3.499053) (2.30696, 3.490018) (2.291191, 3.480861) (2.275558, 3.471582) (2.260065, 3.462181) (2.244717, 3.452652) (2.229523, 3.442993) (2.214491, 3.433198) (2.199626, 3.423264) (2.184932, 3.413192) (2.170403, 3.402984) (2.156033, 3.392649) (2.141814, 3.382195) (2.127746, 3.371622) (2.113839, 3.360926) (2.100115, 3.35009) (2.086611, 3.339089) (2.073357, 3.327901) (2.060375, 3.316512) (2.047663, 3.304925) (2.035185, 3.293172) (2.022889, 3.281294) (2.010735, 3.269328) (1.99872, 3.25728) (1.986904, 3.24511) (1.97544, 3.232709) (1.964531, 3.219927) (1.956415, 3.209277) (1.950744, 3.200996) (1.947157, 3.195338) (1.945413, 3.192475) knots -1 -1 -1 -1 -1 -1 -0.98571429 -0.97142857 -0.95714286 -0.94285714 -0.92857143 -0.91428571 -0.9 -0.88571429 -0.87142857 -0.85714286 -0.84285714 -0.82857143 -0.81428571 -0.8 -0.78571429 -0.77142857 -0.75714286 -0.74285714 -0.72857143 -0.71428571 -0.7 -0.68571429 -0.67142857 -0.65714286 -0.64285714 -0.62857143 -0.61428571 -0.6 -0.58571429 -0.57142857 -0.55714286 -0.54285714 -0.52857143 -0.51428571 -0.5 -0.48571429 -0.47142857 -0.45714286 -0.44285714 -0.42857143 -0.41428571 -0.4 -0.38571429 -0.37142857 -0.35714286 -0.34285714 -0.32857143 -0.31428571 -0.3 -0.28571429 -0.27142857 -0.25714286 -0.24285714 -0.22857143 -0.21428571 -0.2 -0.18571429 -0.17142857 -0.15714286 -0.14285714 -0.12857143 -0.11428571 -0.1 -0.08571429 -0.07142857 -0.05714286 -0.04285714 -0.02857143 -0.01428571 0 0 0 0 0 0
  line L15 (1.945413, 3.192475) -> (1.694974, 2.781499)
  arc A16 (1.694974, 2.781499) -> (0.992145, 3.102471) centre (0, 0) ccw
  line L16 (0.992145, 3.102471) -> (1.138738, 3.560872)
  spline S16 degree 5 poles (1.138738, 3.560872) (1.139759, 3.564065) (1.141686, 3.57048) (1.14423, 3.580189) (1.146964, 3.593298) (1.14948, 3.609912) (1.151345, 3.626697) (1.152805, 3.643596) (1.154042, 3.660567) (1.155126, 3.677588) (1.15605, 3.694659) (1.156762, 3.711786) (1.157194, 3.728981) (1.157299, 3.74625) (1.157076, 3.763593) (1.156546, 3.781003) (1.155748, 3.798471) (1.154724, 3.815986) (1.153502, 3.833541) (1.152092, 3.851134) (1.150492, 3.868762) (1.148692, 3.886426) (1.146682, 3.904128) (1.144455, 3.921867) (1.142013, 3.939642) (1.139363, 3.95745) (1.136514, 3.975289) (1.133473, 3.993155) (1.130249, 4.011046) (1.126842, 4.02896) (1.123255, 4.046897) (1.119486, 4.064854) (1.115535, 4.082832) (1.111401, 4.10083) (1.107087, 4.118845) (1.102594, 4.136877) (1.097926, 4.154924) (1.093084, 4.172985) (1.088071, 4.191057) (1.082888, 4.209141) (1.077536, 4.227235) (1.072016, 4.245337) (1.066329, 4.263447) (1.060475, 4.281564) (1.054455, 4.299686) (1.048271, 4.317813) (1.041923, 4.335943) (1.035413, 4.354075) (1.028742, 4.372208) (1.02191, 4.390342) (1.014919, 4.408474) (1.00777, 4.426605) (1.000462, 4.444732) (0.992997, 4.462856) (0.985375, 4.480974) (0.977598, 4.499087) (0.969665, 4.517193) (0.961578, 4.53529) (0.953338, 4.553379) (0.944944, 4.571458) (0.936398, 4.589526) (0.927701, 4.607583) (0.918852, 4.625628) (0.909852, 4.643659) (0.900703, 4.661676) (0.891405, 4.679677) (0.881958, 4.697662) (0.872362, 4.715629) (0.86262, 4.733577) (0.85273, 4.751506) (0.842694, 4.769417) (0.834548, 4.783729) (0.828372, 4.794455) (0.824226, 4.801602) (0.822146, 4.805174) knots 0 0 0 0 0 0 0.01428571 0.02857143 0.04285714 0.05714286 0.07142857 0.08571429 0.1 0.11428571 0.12857143 0.14285714 0.15714286 0.17142857 0.18571429 0.2 0.21428571 0.22857143 0.24285714 0.25714286 0.27142857 0.28571429 0.3 0.31428571 0.32857143 0.34285714 0.35714286 0.37142857 0.38571429 0.4 0.41428571 0.42857143 0.44285714 0.45714286 0.47142857 0.48571429 0.5 0.51428571 0.52857143 0.54285714 0.55714286 0.57142857 0.58571429 0.6 0.61428571 0.62857143 0.64285714 0.65714286 0.67142857 0.68571429 0.7 0.71428571 0.72857143 0.74285714 0.75714286 0.77142857 0.78571429 0.8 0.81428571 0.82857143 0.84285714 0.85714286 0.87142857 0.88571429 0.9 0.91428571 0.92857143 0.94285714 0.95714286 0.97142857 0.98571429 1 1 1 1 1 1
  arc A17 (0.822146, 4.805174) -> (0.564931, 4.842156) centre (0, 0) ccw
  spline S17 degree 5 poles (0.564931, 4.842156) (0.561928, 4.839315) (0.555937, 4.833626) (0.54699, 4.825074) (0.535141, 4.813636) (0.520466, 4.799279) (0.505925, 4.784862) (0.491521, 4.770385) (0.477252, 4.75585) (0.463121, 4.741255) (0.449128, 4.726603) (0.435273, 4.711894) (0.421558, 4.697128) (0.407984, 4.682307) (0.394552, 4.667432) (0.381261, 4.652503) (0.368114, 4.637521) (0.355111, 4.622487) (0.342253, 4.607401) (0.329541, 4.592263) (0.316976, 4.577076) (0.304558, 4.561838) (0.29229, 4.546552) (0.280171, 4.531218) (0.268203, 4.515836) (0.256386, 4.500408) (0.244723, 4.484933) (0.233213, 4.469414) (0.221859, 4.45385) (0.21066, 4.438243) (0.199619, 4.422593) (0.188738, 4.406901) (0.178017, 4.391167) (0.167458, 4.375393) (0.157061, 4.359579) (0.146829, 4.343726) (0.136761, 4.327835) (0.126859, 4.311907) (0.117125, 4.295942) (0.107561, 4.279941) (0.098171, 4.263905) (0.088956, 4.247835) (0.079919, 4.231731) (0.071063, 4.215595) (0.062387, 4.199426) (0.053892, 4.183227) (0.045577, 4.166998) (0.037442, 4.15074) (0.029491, 4.134455) (0.021731, 4.118142) (0.014172, 4.101801) (0.006821, 4.085434) (-0.000313, 4.069041) (-0.007229, 4.052623) (-0.013933, 4.036181) (-0.020435, 4.019718) (-0.026744, 4.003235) (-0.032862, 3.986735) (-0.038779, 3.970218) (-0.044466, 3.953683) (-0.049879, 3.937127) (-0.05498, 3.92055) (-0.059744, 3.90395) (-0.064174, 3.88733) (-0.068316, 3.870696) (-0.072239, 3.854057) (-0.075995, 3.837419) (-0.079588, 3.820788) (-0.082949, 3.804162) (-0.085889, 3.787531) (-0.088155, 3.770881) (-0.089225, 3.757533) (-0.089519, 3.747501) (-0.089477, 3.740802) (-0.089397, 3.737451) knots -1 -1 -1 -1 -1 -1 -0.98571429 -0.97142857 -0.95714286 -0.94285714 -0.92857143 -0.91428571 -0.9 -0.88571429 -0.87142857 -0.85714286 -0.84285714 -0.82857143 -0.81428571 -0.8 -0.78571429 -0.77142857 -0.75714286 -0.74285714 -0.72857143 -0.71428571 -0.7 -0.68571429 -0.67142857 -0.65714286 -0.64285714 -0.62857143 -0.61428571 -0.6 -0.58571429 -0.57142857 -0.55714286 -0.54285714 -0.52857143 -0.51428571 -0.5 -0.48571429 -0.47142857 -0.45714286 -0.44285714 -0.42857143 -0.41428571 -0.4 -0.38571429 -0.37142857 -0.35714286 -0.34285714 -0.32857143 -0.31428571 -0.3 -0.28571429 -0.27142857 -0.25714286 -0.24285714 -0.22857143 -0.21428571 -0.2 -0.18571429 -0.17142857 -0.15714286 -0.14285714 -0.12857143 -0.11428571 -0.1 -0.08571429 -0.07142857 -0.05714286 -0.04285714 -0.02857143 -0.01428571 0 0 0 0 0 0
  line L17 (-0.089397, 3.737451) -> (-0.077889, 3.256319)
  arc A18 (-0.077889, 3.256319) -> (-0.842677, 3.146359) centre (0, 0) ccw
  line L18 (-0.842677, 3.146359) -> (-0.967186, 3.611244)
  spline S18 degree 5 poles (-0.967186, 3.611244) (-0.968053, 3.614482) (-0.9699, 3.620921) (-0.973009, 3.630464) (-0.977796, 3.64297) (-0.984661, 3.658307) (-0.992167, 3.673436) (-1.000076, 3.688442) (-1.00821, 3.703387) (-1.0165, 3.718293) (-1.024952, 3.733153) (-1.033613, 3.747946) (-1.042546, 3.762644) (-1.051794, 3.77723) (-1.061358, 3.791698) (-1.071217, 3.806058) (-1.081331, 3.820322) (-1.091662, 3.834503) (-1.102181, 3.848611) (-1.112878, 3.862648) (-1.123755, 3.876612) (-1.134819, 3.8905) (-1.146081, 3.904305) (-1.157545, 3.918024) (-1.169209, 3.931657) (-1.181066, 3.945206) (-1.193107, 3.958672) (-1.205324, 3.972058) (-1.217709, 3.985365) (-1.23026, 3.998594) (-1.242975, 4.011743) (-1.255855, 4.024813) (-1.268898, 4.037801) (-1.282106, 4.050706) (-1.295475, 4.063529) (-1.309003, 4.07627) (-1.322688, 4.088928) (-1.336525, 4.101504) (-1.350513, 4.113997) (-1.36465, 4.126408) (-1.378934, 4.138736) (-1.393365, 4.150981) (-1.407941, 4.163141) (-1.42266, 4.175217) (-1.437522, 4.187208) (-1.452525, 4.199113) (-1.467666, 4.210933) (-1.482946, 4.222668) (-1.498362, 4.234316) (-1.513912, 4.245877) (-1.529597, 4.257351) (-1.545413, 4.268738) (-1.561362, 4.280037) (-1.57744, 4.291248) (-1.593647, 4.30237) (-1.609983, 4.313402) (-1.626445, 4.324345) (-1.643032, 4.335197) (-1.659744, 4.345959) (-1.676579, 4.356631) (-1.693537, 4.36721) (-1.710616, 4.377699) (-1.727816, 4.388095) (-1.745135, 4.398398) (-1.762573, 4.408608) (-1.780127, 4.418725) (-1.797798, 4.428747) (-1.815583, 4.438674) (-1.833483, 4.448506) (-1.851496, 4.458242) (-1.869622, 4.467883) (-1.884213, 4.47552) (-1.895207, 4.481204) (-1.902559, 4.484975) (-1.90624, 4.486856) knots 0 0 0 0 0 0 0.01428571 0.02857143 0.04285714 0.05714286 0.07142857 0.08571429 0.1 0.11428571 0.12857143 0.14285714 0.15714286 0.17142857 0.18571429 0.2 0.21428571 0.22857143 0.24285714 0.25714286 0.27142857 0.28571429 0.3 0.31428571 0.32857143 0.34285714 0.35714286 0.37142857 0.38571429 0.4 0.41428571 0.42857143 0.44285714 0.45714286 0.47142857 0.48571429 0.5 0.51428571 0.52857143 0.54285714 0.55714286 0.57142857 0.58571429 0.6 0.61428571 0.62857143 0.64285714 0.65714286 0.67142857 0.68571429 0.7 0.71428571 0.72857143 0.74285714 0.75714286 0.77142857 0.78571429 0.8 0.81428571 0.82857143 0.84285714 0.85714286 0.87142857 0.88571429 0.9 0.91428571 0.92857143 0.94285714 0.95714286 0.97142857 0.98571429 1 1 1 1 1 1
  arc A19 (-1.90624, 4.486856) -> (-2.142617, 4.378906) centre (0, 0) ccw